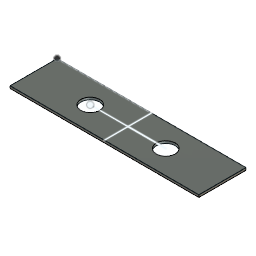
Drill guide 16mm (Autodesk Fusion 360 design; units mm, degrees)
Autodesk Fusion 360 part; units mm, degrees
sketch "Sketch1" plane through (0, 0, 0) normal (0, 0, 1) x (1, 0, 0)
  line L0 (0, 0) -> (40, 0)
  line L1 (40, 0) -> (40, 10)
  line L2 (40, 10) -> (0, 10)
  line L3 (0, 10) -> (0, 0)
  dimension "d1" = 40
  dimension "d2" = 10
  constraint horizontal L0
  constraint vertical L1
  constraint horizontal L2
  constraint vertical L3
  constraint coincident L0.start L3.end
  measures "d1" distance of L0.start L0.end
  measures "d2" distance of L0.start L2.end
extrude "Extrude1" add sketch "Sketch1" along normal blind 0.5
sketch "Sketch2" plane through (0, 0, 0.5) normal (0, 0, 1) x (-1, 0, 0)
  line L0 (0, -10) -> (0, 0)
  line L1 (0, 0) -> (-40, 0)
  line L2 (-40, 0) -> (-40, -10)
  line L3 (-40, -10) -> (0, -10)
  line L4 (0, -10) -> (-20, -10)
  line L5 (-20, -10) -> (-20, 0)
  line L6 (-20, -5) -> (-28, -5)
  line L7 (-28, -5) -> (-12, -5)
  dimension "d5" = 20
  dimension "d6" = 8
  dimension "d7" = 16
  constraint coincident L0.start L3.end
  constraint midpoint L3 L4.end
  constraint midpoint L1 L5.end
  constraint midpoint L5 L6.start
  constraint perpendicular L5 L6
  constraint perpendicular L5 L7
  measures "d5" distance of L0.start L4.end
  measures "d6" distance of L6.start L6.end
  measures "d7" distance of L6.end L7.end
sketch "Sketch3" plane through (0, 0, 0.5) normal (0, 0, 1) x (-1, 0, 0)
  circle A0 centre (-12, -5) radius 2
  circle A1 centre (-28, -5) radius 2
  dimension "d8" = 4
  dimension "d9" = 4
  measures "d8" diameter of A0
  measures "d9" diameter of A1
extrude "Extrude2" cut sketch "Sketch3" against normal blind 6754
